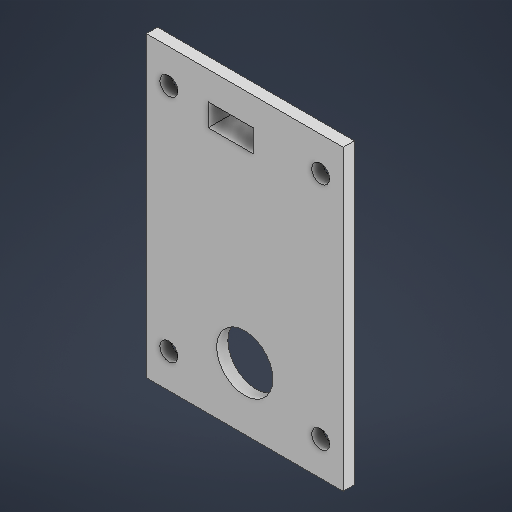
# Autodesk Inventor part: supportscd40
Saved by Autodesk Inventor 2026.1 (Build 301233020, 233B)
## iProperties
Created: 2026-06-04
Part Number: supportscd40
Material: Générique
Document SubType Name: Modeling
Designer: matpo
Density: 1 g/cm^3
Appearance: Par défaut
Author: matpo
Autodesk Inventor part; units mm, degrees
ref_plane "YZ Plane" through (0, 0, 0) normal (1, 0, 0) x (0, 1, 0)
ref_plane "XZ Plane" through (0, 0, 0) normal (0, 1, 0) x (-1, 0, 0)
sketch "Esquisse1" plane through (0, 0, 0) normal (0, 0, 1) x (1, 0, 0)
  line L0 (-50.6, 34) -> (-15.6, 34)
  line L1 (-15.6, 34) -> (-15.6, -19)
  line L2 (-15.6, -19) -> (-50.6, -19)
  line L3 (-50.6, -19) -> (-50.6, 34)
  line L4 (-15.6, 34) -> (-50.6, -19) construction
  line L5 (-15.6, -19) -> (-50.6, 34) construction
  line L6 (-40.6, -15) -> (-25.6, 15) construction
  line L7 (-25.6, -15) -> (-40.6, 15) construction
  circle A0 centre (-46.6, -12.9429) radius 1.6
  circle A1 centre (-19.6, -12.9429) radius 1.6
  circle A2 centre (-19.6, 27.9429) radius 1.6
  circle A3 centre (-46.6, 27.9429) radius 1.6
  line L8 (-40.6, 30) -> (-30.6, 30)
  line L9 (-30.6, 30) -> (-30.6, 24)
  line L10 (-30.6, 24) -> (-40.6, 24)
  line L11 (-40.6, 24) -> (-40.6, 30)
  circle A4 centre (-33.1, -8) radius 5
  line L12 (-25.6, -8) -> (-33.1, -8) construction
  line L13 (-33.1, -8) -> (-40.6, -8) construction
  line L14 (-39.6, 25) -> (-31.6, 25)
  line L15 (-31.6, 25) -> (-31.6, 29)
  line L16 (-31.6, 29) -> (-39.6, 29)
  line L17 (-39.6, 29) -> (-39.6, 25)
  line L18 (70.1, 37.5) -> (70.1, -37.5) projected
  line L19 (72.5, 37.5) -> (72.5, -37.5) projected
  arc A5 (72.5, 37.5) -> (62.5, 47.5) centre (62.5, 37.5) ccw projected
  line L20 (2.4, 47.5) -> (62.5, 47.5) projected
  arc A6 (8, 45.1) -> (6.4957, 44.0449) centre (8, 43.5) ccw projected
  line L21 (8, 45.1) -> (62.5, 45.1) projected
  arc A7 (70.1, 37.5) -> (62.5, 45.1) centre (62.5, 37.5) ccw projected
  arc A8 (6.4957, -44.0449) -> (8, -45.1) centre (8, -43.5) ccw projected
  line L22 (62.5, -47.5) -> (2.4, -47.5) projected
  arc A9 (62.5, -47.5) -> (72.5, -37.5) centre (62.5, -37.5) ccw projected
  arc A10 (62.5, -45.1) -> (70.1, -37.5) centre (62.5, -37.5) ccw projected
  line L23 (62.5, -45.1) -> (8, -45.1) projected
  arc A11 (2.4, -47.5) -> (6.4957, -44.0449) centre (0, -40.5) ccw projected
  arc A12 (6.4957, 44.0449) -> (2.4, 47.5) centre (0, 40.5) ccw projected
  point P0 (0, 0)
  point P1 (-33.1, 7.5)
  point P2 (-33.1, 0)
  point P3 (8, 43.5)
  point P4 (8, -43.5)
  dimension "d3" = 3.2
  dimension "d4" = 4
  dimension "d5" = 4
  dimension "d6" = 4
  dimension "d7" = 4
  dimension "d10" = 6
  dimension "d20" = 4
  dimension "d27" = 1
  dimension "d32" = 10
  constraints: 36 end point, 6 parallel, 5 centre point, 5 point on line, 3 equal radius, 3 perpendicular, 2 horizontal, 2 horizontal alignment, 2 midpoint, 1 coincident, 1 collinear, 1 vertical alignment, 3 other
  measures "d3" diameter of A0
  measures "d4" distance from line of L3 A0.centre
  measures "d5" distance from line of L1 A1.centre
  measures "d6" distance from line of L3 A3.centre
  measures "d7" distance from line of L1 A2.centre
  measures "d10" distance of L8.end L9.end
  measures "d20" distance between parallel lines of L0 L8
  measures "d27" distance between parallel lines of L10 L14
  measures "d32" diameter of A4
extrude "Extrusion1" add sketch "Esquisse1" along normal blind 2 contours L0 L1 L2 L3 | L8 L9 L10 L11
sketch "Esquisse2" plane through (0, 0, 0) normal (0, 0, -1) x (-1, 0, 0)
  line L0 (50.6, -19) -> (15.6, -19) projected
  line L1 (50.6, 34) -> (50.6, -19) projected
  line L2 (15.6, 34) -> (50.6, 34) projected
  line L3 (15.6, -19) -> (15.6, 34) projected
  circle A0 centre (46.6, -12.9429) radius 1.6 projected
  circle A1 centre (19.6, -12.9429) radius 1.6 projected
  circle A2 centre (19.6, 27.9429) radius 1.6 projected
  circle A3 centre (46.6, 27.9429) radius 1.6 projected
  line L4 (42.6, 32) -> (42.6, -17)
  line L5 (42.6, -17) -> (23.6, -17)
  line L6 (23.6, -17) -> (23.6, 32)
  line L7 (23.6, 32) -> (42.6, 32)
  line L8 (-70.1, 37.5) -> (-70.1, -37.5) projected
  line L9 (-72.5, 37.5) -> (-72.5, -37.5) projected
  arc A4 (-62.5, 47.5) -> (-72.5, 37.5) centre (-62.5, 37.5) ccw projected
  line L10 (-2.4, 47.5) -> (-62.5, 47.5) projected
  arc A5 (-6.4957, 44.0449) -> (-8, 45.1) centre (-8, 43.5) ccw projected
  line L11 (-8, 45.1) -> (-62.5, 45.1) projected
  arc A6 (-62.5, 45.1) -> (-70.1, 37.5) centre (-62.5, 37.5) ccw projected
  arc A7 (-8, -45.1) -> (-6.4957, -44.0449) centre (-8, -43.5) ccw projected
  line L12 (-62.5, -47.5) -> (-2.4, -47.5) projected
  arc A8 (-72.5, -37.5) -> (-62.5, -47.5) centre (-62.5, -37.5) ccw projected
  arc A9 (-70.1, -37.5) -> (-62.5, -45.1) centre (-62.5, -37.5) ccw projected
  line L13 (-62.5, -45.1) -> (-8, -45.1) projected
  arc A10 (-6.4957, -44.0449) -> (-2.4, -47.5) centre (0, -40.5) ccw projected
  arc A11 (-2.4, 47.5) -> (-6.4957, 44.0449) centre (0, 40.5) ccw projected
  point P0 (0, 0)
  point P1 (-8, 43.5)
  point P2 (-8, -43.5)
  constraints: 8 end point, 2 parallel, 1 perpendicular
ref_plane "Plan de construction2" through (-33.1, -19, 0) normal (-1, 0, 0) x (0, 0, 1)
sketch "Esquisse5" plane through (-33.1, -19, 0) normal (-1, 0, 0) x (0, 0, 1)
  line L0 (0.5, 2.5) -> (-0.5, 2.5)
  line L1 (-0.5, 2.5) -> (-0.5, 1.5)
  line L2 (-0.5, 1.5) -> (0.5, 1.5)
  line L3 (0.5, 1.5) -> (0.5, 2.5)
  line L4 (0.5, 2.5) -> (-0.5, 1.5) construction
  line L5 (-0.5, 2.5) -> (0.5, 1.5) construction
  point P0 (0, 19)
  point P1 (0, 2)
  point P2 (0, 2)
  point P3 (0, 2)
  dimension "d22" = 1
  dimension "d23" = 1
  constraints: 12 end point, 2 midpoint, 2 parallel, 1 horizontal, 1 perpendicular
  measures "d22" distance of L2.end L1.end
  measures "d23" distance of L1.end L0.end
sweep "Balayage2" cut profiles "Esquisse5" path "Esquisse2" path curves L7 L6 L5 L4
sketch "Esquisse6" plane through (0, 0, 0) normal (0, 0, -1) x (-1, 0, 0)
  line L0 (30.6, 30) -> (30.6, 15) projected
  line L1 (31.6, 25) -> (31.6, 29) projected
  line L2 (39.6, 29) -> (39.6, 25) projected
  line L3 (39.6, 29) -> (31.6, 29) projected
  line L4 (39.6, 25) -> (31.6, 25) projected
  line L5 (40.6, -15) -> (40.6, 30) projected
  line L6 (40.6, 30) -> (30.6, 30) projected
  line L7 (31.6, 25) -> (39.6, 25)
  line L8 (39.6, 25) -> (39.6, 29)
  line L9 (39.6, 29) -> (31.6, 29)
  line L10 (31.6, 29) -> (31.6, 25)
  line L11 (31.6, 25) -> (39.6, 29) construction
  line L12 (39.6, 25) -> (31.6, 29) construction
  line L13 (30.9, 24.3) -> (40.3, 24.3)
  line L14 (40.3, 24.3) -> (40.3, 29.7)
  line L15 (40.3, 29.7) -> (30.9, 29.7)
  line L16 (30.9, 29.7) -> (30.9, 24.3)
  line L17 (30.9, 24.3) -> (40.3, 29.7) construction
  line L18 (40.3, 24.3) -> (30.9, 29.7) construction
  line L19 (31.6, 25) -> (39.6, 29) construction
  line L20 (39.6, 25) -> (31.6, 29) construction
  point P0 (0, 0)
  point P1 (35.6, 27)
  dimension "d28" = 0.3
  dimension "d29" = 0.3
  constraints: 28 end point, 6 midpoint, 5 equal length, 2 horizontal, 2 perpendicular
  measures "d28" distance between parallel lines of L5 L14
  measures "d29" distance between parallel lines of L6 L15
extrude "Extrusion2" add sketch "Esquisse6" along normal blind 2
equation "\"d5\" = d4"
equation "\"d6\" = d4"
equation "\"d7\" = d6"
